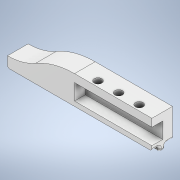
# Autodesk Inventor part: P2_V1_001
Saved by Autodesk Inventor 2020 (Build 240168000, 168)
## iProperties
Created: 2022-06-02
Part Number: P2_V1_001
Material: ABS Plastic
Document SubType Name: Modeling
Designer: drago
Density: 1.06 g/cm^3
Appearance: Smooth - White
Author: drago
Autodesk Inventor part; units mm, degrees
ref_plane "YZ Plane" through (0, 0, 0) normal (1, 0, 0) x (0, 1, 0)
ref_plane "XZ Plane" through (0, 0, 0) normal (0, 1, 0) x (-1, 0, 0)
ref_plane "XY Plane" through (0, 0, 0) normal (0, 0, 1) x (1, 0, 0)
sketch "Sketch1" plane through (0, 0, 0) normal (0, 0, 1) x (1, 0, 0)
  line L0 (0, 45) -> (-280, 45)
  line L1 (-280, 45) -> (-280, 100)
  line L2 (-280, 100) -> (0, 100)
  line L3 (0, 100) -> (0, 45)
  point P0 (0, 0)
  dimension "d0" = 280
  dimension "d47" = 0
  dimension "d48" = 55
  constraints: 8 end point, 2 parallel, 1 horizontal, 1 perpendicular, 1 other
  measures "d0" distance of L1.end L2.end
  measures "d47" distance from line of point (0, 0) L3
  measures "d48" distance of L0.end L1.end
extrude "Extrusion1" add sketch "Sketch1" along normal blind 40
sketch "Sketch2" plane through (0, 0, 40) normal (0, 0, 1) x (1, 0, 0)
  line L0 (0, 100) -> (0, 100)
  line L1 (-280, 100) -> (-280, 45) projected
  line L2 (0, 45) -> (0, 100) projected
  line L3 (0, 100) -> (-280, 100) projected
  line L4 (-280, 100) -> (-280, 45) projected
  line L5 (-280, 45) -> (0, 45) projected
  line L6 (-150, 54) -> (-0.9428, 54)
  line L7 (-150, 85) -> (-150, 54)
  line L8 (0, 85) -> (0, 54.0297)
  line L9 (-0.9428, 54) -> (0, 54)
  line L10 (0, 54) -> (0, 54.0297)
  line L11 (-150, 85) -> (0, 85)
  line L12 (0, 45) -> (0, 100) projected
  point P0 (-180, 55)
  dimension "d231" = 0
  dimension "d233" = 150
  constraints: 14 end point, 2 horizontal, 2 vertical, 1 collinear, 1 perpendicular, 1 point on line
  measures "d231" distance between parallel lines of L2 L8
  measures "d233" distance of L7.start L8.start
sketch "Sketch3" plane through (0, 0, 40) normal (0, 0, 1) x (1, 0, 0)
  line L0 (0, 100) -> (-280, 100) projected
  line L1 (-280, 100) -> (-280, 45) projected
  line L2 (-280, 45) -> (0, 45) projected
  line L3 (0, 45) -> (0, 100) projected
  line L4 (0, 45) -> (0, 100) projected
  line L5 (0, 100) -> (-150, 100)
  line L6 (0, 100) -> (-280, 100) projected
  arc A0 (-280, 65) -> (-225.3103, 79.7241) centre (-280, 173.9286) ccw
  arc A1 (-150, 100) -> (-225.3103, 79.7241) centre (-150, -50) ccw
  line L7 (-280, 100) -> (-280, 45) projected
  line L8 (-150, 100) -> (-280, 100)
  line L9 (-280, 45) -> (-280, 100)
  point P0 (-200, 100)
  point P1 (-280, 65)
  dimension "d203" = 20
  dimension "d207" = 150
  dimension "d208" = 150
  constraints: 6 end point, 5 point on circle, 4 point on line, 3 tangent, 2 centre point, 2 collinear, 1 line through centre
  measures "d203" distance of L1.end A0.start
  measures "d207" radius of A1
  measures "d208" distance of L0.start L5.end
extrude "Extrusion3" cut sketch "Sketch3" against normal up to next contours A1 A0 L1 L0
extrude "Extrusion6" cut sketch "Sketch2" against normal blind 21 contours L2 L9 L6 L7 L11
sketch "Sketch10" plane through (0, 45, 0) normal (1, 0, 0) x (0, 0, -1)
  line L0 (0, 0) -> (-40, 0) projected
  line L1 (0, 0) -> (-14.25, 0)
  line L2 (-40, 0) -> (-25.75, 0)
  line L3 (0, 0) -> (-40, 0) projected
  line L4 (-14.25, 0) -> (-14.25, -10)
  line L5 (-14.25, -10) -> (-25.75, -10)
  line L6 (-25.75, -10) -> (-25.75, 0)
  point P0 (0, -45)
  point P1 (-14.25, 0)
  point P2 (-25.75, 0)
  dimension "d95" = 11.5
  dimension "d96" = 10
  constraints: 10 end point, 2 perpendicular, 2 point on line, 1 collinear, 1 vertical
  measures "d95" distance of L4.end L5.end
  measures "d96" distance of L5.end L2.end
extrude "Extrusion10" add sketch "Sketch10" against normal up to surface (280 mm away)
fillet "Fillet3" radius 4 4 edges at (-140, 45, 14.25) (-140, 45, 25.75) (-140, 35, 25.75) (-140, 35, 14.25)
fillet "Fillet4" radius 4 18 edges at (0, 40, 25.75) (0, 43.8284, 26.9216) (0, 45, 34.875) (0, 35, 20) (0, 36.1716, 15.4216) (0, 40, 14.25) (0, 43.8284, 13.0784) (0, 45, 5.125) (0, 36.1716, 24.5784) (-280, 43.8284, 26.9216) (-280, 40, 25.75) (-280, 36.1716, 24.5784) (-280, 35, 20) (-280, 36.1716, 15.4216) (-280, 40, 14.25) (-280, 43.8284, 13.0784) (-280, 45, 5.125) (-280, 45, 34.875)
sketch "Sketch21" plane through (0, 0, 40) normal (0, 0, 1) x (1, 0, 0)
  arc A0 (-280, 49) -> (-276, 45) centre (-276, 49) ccw projected
  line L0 (-276, 45) -> (-4, 45) projected
  arc A1 (-4, 45) -> (0, 49) centre (-4, 49) ccw projected
  line L1 (0, 85) -> (0, 100) projected
  line L2 (0, 100) -> (-150, 100) projected
  line L3 (-280, 65) -> (-280, 49) projected
  line L4 (-150, 54) -> (-150, 85) projected
  line L5 (0, 54) -> (-150, 54) projected
  line L6 (-30, 85) -> (-30, 54) projected
  line L7 (-30, 85) -> (0, 85)
  line L8 (0, 49) -> (0, 100) projected
  line L9 (-30, 54) -> (0, 54)
  line L10 (0, 85) -> (0, 54)
  line L11 (-30, 85) -> (-30, 54) projected
  line L12 (-30, 85) -> (-30, 54)
  line L13 (0, 49) -> (0, 100) projected
  arc A2 (-150, 100) -> (-225.3103, 79.7241) centre (-150, -50) ccw projected
  arc A3 (-280, 65) -> (-225.3103, 79.7241) centre (-280, 173.9286) ccw projected
  line L14 (0, 49) -> (0, 54) projected
  line L15 (-150, 85) -> (0, 85) projected
  point P0 (0, 0)
  point P1 (-180, 85)
  point P2 (-30, 54.0297)
  point P3 (0, 85)
  constraints: 8 end point, 3 point on line, 1 collinear, 1 horizontal, 1 parallel, 1 perpendicular, 1 vertical
extrude "Extrusion18" cut sketch "Sketch21" against normal blind 21 contours L5 L6 L7 L8
sketch "Sketch24" plane through (0, 0, 0) normal (0, 0, -1) x (-1, 0, 0)
  line L0 (0, 100) -> (150, 100) projected
  line L1 (280, 65) -> (280, 49) projected
  line L2 (276, 45) -> (4, 45) projected
  line L3 (0, 49) -> (0, 100) projected
  arc A0 (0, 49) -> (4, 45) centre (4, 49) ccw projected
  line L4 (276, 45) -> (4, 45) projected
  arc A1 (276, 45) -> (280, 49) centre (276, 49) ccw projected
  line L5 (280, 65) -> (280, 49) projected
  line L6 (0, 100) -> (150, 100) projected
  line L7 (5, 49) -> (5, 90)
  line L8 (5, 90) -> (5, 95)
  line L9 (5, 49) -> (276, 49)
  line L10 (5, 49) -> (276, 49) construction
  arc A2 (225.3103, 79.7241) -> (280, 65) centre (280, 173.9286) ccw projected
  arc A3 (225.3103, 79.7241) -> (150, 100) centre (150, -50) ccw projected
  line L11 (276, 49) -> (276, 59)
  arc A4 (182.2159, 80.2932) -> (276, 59) centre (276, 276.1781) ccw
  line L12 (5, 95) -> (117.4414, 95)
  arc A5 (182.2159, 80.2932) -> (117.4414, 95) centre (117.4414, -55) ccw
  point P0 (0, 0)
  point P1 (30, 85)
  point P2 (280, 100)
  point P3 (156.2468, 95)
  dimension "d214" = 150
  dimension "d215" = 10
  dimension "d217" = 5
  dimension "d230" = 5
  constraints: 12 end point, 5 point on circle, 2 centre point, 2 horizontal, 2 tangent, 1 coincident, 1 collinear, 1 line through centre, 1 point on line, 1 vertical
  measures "d214" radius of A5
  measures "d215" distance of L10.end L11.end
  measures "d217" distance between parallel lines of L0 L12
  measures "d230" distance from line of L3 L7.start
extrude "Extrusion19" cut sketch "Sketch24" against normal blind 12 contours L7 L8 L12 A5 A4 L11 L9
fillet "Fillet19" radius 2 6 edges at (-150.653, 91.2771, 12) (-227.9145, 64.3902, 12) (-61.2207, 95, 12) (-5, 72, 12) (-140.5, 49, 12) (-276, 54, 12)
sketch "Sketch25" plane through (0, 100, 40) normal (0, 1, 0) x (1, 0, 0)
  line L0 (-180, 21) -> (-30, 21) projected
  line L1 (-150, 40) -> (-150, 0) projected
  line L2 (0, 0) -> (-150, 0) projected
  line L3 (0, 40) -> (0, 0) projected
  line L4 (0, 40) -> (-150, 40) projected
  line L5 (-150, 40) -> (-150, 0) construction
  line L6 (-150, 10.5) -> (0, 10.5) construction
  line L7 (0, 10.25) -> (0, 18.25) construction
  circle A0 centre (-115, 10.5) radius 7.5
  circle A1 centre (-75, 10.5) radius 7.5
  circle A2 centre (-35, 10.5) radius 7.5
  line L8 (0, 40) -> (-150, 40) construction
  line L9 (-135, 40) -> (-135, 0) construction
  line L10 (-276, 0) -> (-4, 0) construction
  line L11 (-15, 40) -> (-15, 0) construction
  line L12 (-115, 10.5) -> (-115, -10.3661)
  line L13 (-115, -10.3661) -> (-75, -10.3661)
  line L14 (-75, -10.3661) -> (-75, 10.5)
  line L15 (-75, -10.3661) -> (-35, -10.3661)
  line L16 (-35, -10.3661) -> (-35, 10.5)
  dimension "d219" = 15
  dimension "d220" = 15
  dimension "d221" = 15
  dimension "d222" = 10.5
  dimension "d223" = 15
  dimension "d224" = 15
  dimension "d225" = 20
  dimension "d226" = 20
  constraints: 16 end point, 9 point on line, 5 perpendicular, 3 centre point, 1 collinear, 1 midpoint, 1 parallel, 1 vertical
  measures "d219" diameter of A0
  measures "d220" diameter of A1
  measures "d221" diameter of A2
  measures "d222" distance between parallel lines of L2 L6
  measures "d223" distance between parallel lines of L9 L1
  measures "d224" distance between parallel lines of L3 L11
  measures "d225" distance from line of L9 L12.start
  measures "d226" distance from line of L11 L16.end
extrude "Extrusion20" cut sketch "Sketch25" against normal up to surface (15 mm away) contours A0 | A1 | A2
body "Solid1"
